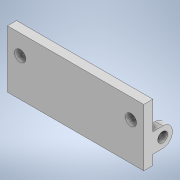
# Autodesk Inventor part: suport_sharp
Saved by Autodesk Inventor 2020 (Build 240168000, 168)
## iProperties
Created: 2023-10-29
Part Number: suport_sharp
Material: Generic
Document SubType Name: Modeling
Designer: user
Density: 1 g/cm^3
Appearance: Default
Author: user
Autodesk Inventor part; units mm, degrees
ref_plane "YZ Plane" through (0, 0, 0) normal (1, 0, 0) x (0, 1, 0)
ref_plane "XZ Plane" through (0, 0, 0) normal (0, 1, 0) x (-1, 0, 0)
ref_plane "XY Plane" through (0, 0, 0) normal (0, 0, 1) x (1, 0, 0)
sketch "Sketch1" plane through (0, 0, 0) normal (0, 0, 1) x (1, 0, 0)
  line L0 (-36.7911, 14.6805) -> (8.2089, 14.6805)
  line L1 (8.2089, 14.6805) -> (8.2089, -4.3195)
  line L2 (8.2089, -4.3195) -> (-36.7911, -4.3195)
  line L3 (-36.7911, -4.3195) -> (-36.7911, 14.6805)
  line L4 (-36.7911, 1.6805) -> (8.2089, 1.6805) construction
  line L5 (-36.7911, 8.1805) -> (8.2089, 8.1805) construction
  circle A0 centre (-32.5911, 8.1805) radius 1.85
  circle A1 centre (4.0089, 8.1805) radius 1.85
  point P0 (0, 0)
  dimension "d0" = 45
  dimension "d1" = 19
  dimension "d2" = 13
  dimension "d3" = 6.5
  dimension "d4" = 3.7
  dimension "d5" = 3.7
  dimension "d6" = 4.2
  dimension "d7" = 4.2
  constraints: 12 end point, 6 point on line, 2 centre point, 2 horizontal, 2 parallel, 2 perpendicular
  measures "d0" distance of L1.end L2.end
  measures "d1" distance of L0.end L1.end
  measures "d2" distance between parallel lines of L4 L0
  measures "d3" distance from line of L0 L5.start
  measures "d4" diameter of A0
  measures "d5" diameter of A1
  measures "d6" distance of L5.end A1.centre
  measures "d7" distance from line of L3 A0.centre
extrude "Extrusion1" add sketch "Sketch1" along normal blind 3
sketch "Sketch3" plane through (8.2089, -4.3195, 0) normal (1, 0, 0) x (0, 0, -1)
  line L0 (0, 0) -> (0, 19) projected
  line L1 (0, 19) -> (-3, 19) projected
  line L2 (-3, 0) -> (-3, 19) projected
  line L3 (0, 0) -> (-3, 0) projected
  circle A0 centre (3.25, 6.5) radius 3.25
  line L4 (0, 0) -> (0, 19) projected
  circle A1 centre (3.25, 6.5) radius 1.65
  point P0 (0, 4.3195)
  dimension "d10" = 6.5
  dimension "d11" = 19
  dimension "d12" = 12.5
  dimension "d15" = 3.3
  constraints: 2 centre point, 1 coincident, 1 tangent
  measures "d10" diameter of A0
  measures "d11" distance of L0.start L0.end
  measures "d12" distance from line of A0.centre L1
  measures "d15" diameter of A1
extrude "Extrusion2" add sketch "Sketch3" against normal blind 45 contours A0
sketch "Sketch5" plane through (8.2089, 2.1805, -3.25) normal (1, 0, 0) x (0, 0, -1)
  circle A0 centre (0, 0) radius 3.25 projected
  circle A1 centre (0, 0) radius 1.65 projected
  line L0 (-3.25, -6.5) -> (-3.25, 0) projected
  line L1 (-3.25, 0) -> (-3.25, 12.5) projected
  line L2 (-3.25, 12.5) -> (-6.25, 12.5) projected
  line L3 (-6.25, -6.5) -> (-6.25, 12.5) projected
  line L4 (-3.25, -6.5) -> (-6.25, -6.5) projected
  circle A2 centre (0, 0) radius 3.25 projected
  line L5 (0, 3.25) -> (-3.25, 3.25)
  line L6 (0, -3.25) -> (-3.25, -3.25)
  line L7 (-3.25, 0) -> (-3.25, -6.5) projected
  line L8 (-3.25, 0) -> (-3.25, 12.5) projected
  line L9 (-3.25, 3.25) -> (-3.25, 0)
  line L10 (-3.25, 0) -> (-3.25, -3.25)
  point P0 (-3.25, -2.1805)
  constraints: 8 end point, 2 point on circle, 1 collinear, 1 midpoint, 1 perpendicular, 1 point on line, 1 tangent, 1 vertical, 1 other
extrude "Extrusion3" add sketch "Sketch5" against normal blind 45 contours A0 L1 L5 | L6 L0 A0
sketch "Sketch6" plane through (-36.7911, -4.3195, 0) normal (0, -1, 0) x (1, 0, 0)
  line L0 (0, 0) -> (45, 0) projected
  line L1 (45, 0) -> (45, 3) projected
  line L2 (0, 3) -> (45, 3) projected
  line L3 (0, 0) -> (0, 3) projected
  line L4 (45, 0) -> (0, 0) projected
  line L5 (45, -6.5) -> (0, -6.5) projected
  line L6 (42.5, 0) -> (2.5, 0)
  line L7 (2.5, 0) -> (2.5, -6.5)
  line L8 (2.5, -6.5) -> (42.5, -6.5)
  line L9 (42.5, -6.5) -> (42.5, 0)
  point P0 (36.7911, 0)
  dimension "d18" = 2.5
  dimension "d19" = 2.5
  constraints: 8 end point, 3 point on line, 2 parallel, 1 horizontal, 1 perpendicular
  measures "d18" distance from line of L3 point (2.5, 0)
  measures "d19" distance from line of L1 L6.start
extrude "Extrusion4" cut sketch "Sketch6" against normal blind 45 contours L0 L9 L5 L7
equation "\"d3\" = 0.5 * d2"
equation "\"d7\" = d6"
body "Solid1"
